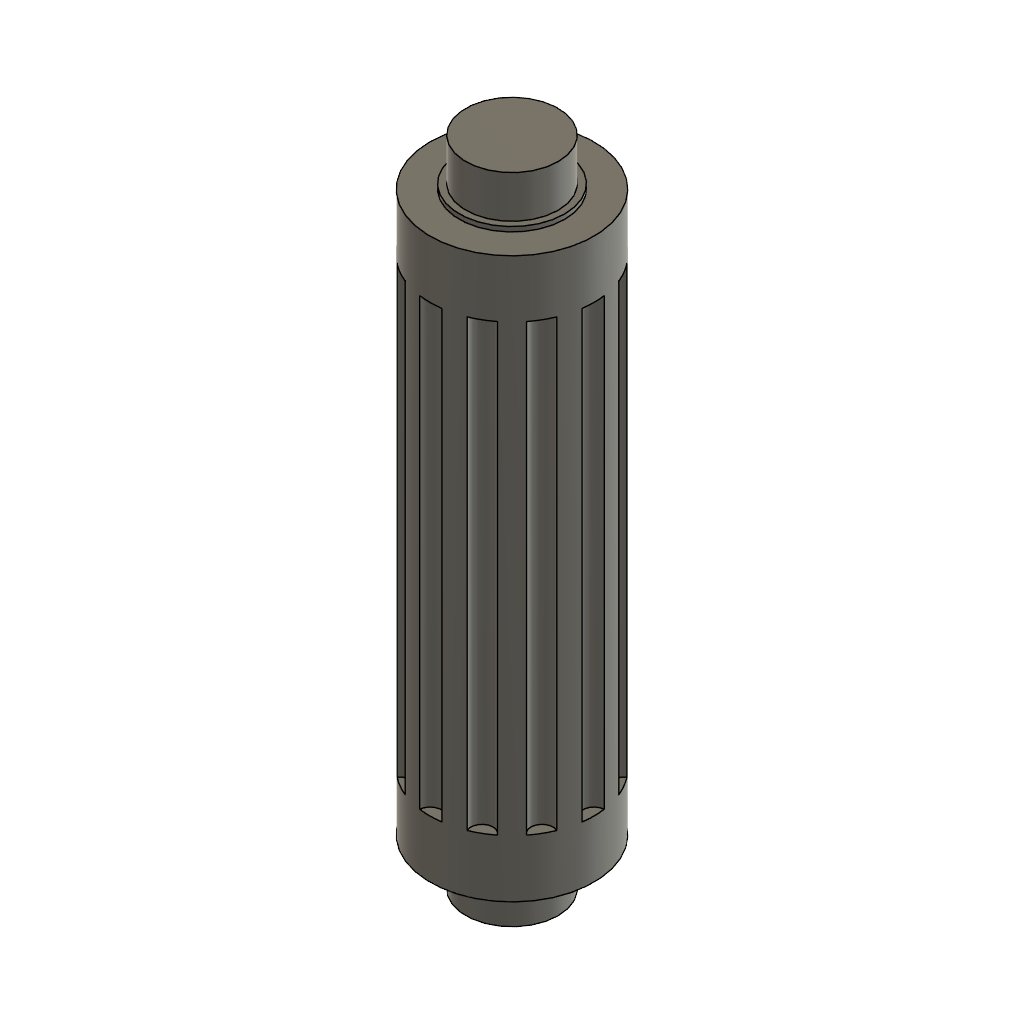
02-10_아이들롤러 (Autodesk Fusion 360 design; units mm, degrees)
Autodesk Fusion 360 part; units mm, degrees
sketch "스케치1" plane through (0, 0, 0) normal (0, 1, 0) x (1, 0, 0)
  circle A0 centre (0, 0) radius 7
  dimension "d1" = 14
  constraint coincident A0.centre origin
  measures "d1" diameter of A0
extrude "돌출1" add sketch "스케치1" along normal blind 47.8
sketch "스케치2" plane through (0, 47.8, 0) normal (0, 1, 0) x (-1, 0, 0)
  circle A0 centre (0, 0) radius 7
  circle A1 centre (0, 0) radius 4.5
  dimension "d4" = 9
  constraint coincident A0.centre A1.centre
  measures "d4" diameter of A1
extrude "돌출2" add sketch "스케치2" along normal blind 0.4 contours A1
sketch "스케치3" plane through (0, 48.2, 0) normal (0, 1, 0) x (-1, 0, 0)
  circle A0 centre (0, 0) radius 4.5
  circle A1 centre (0, 0) radius 3.95
  dimension "d7" = 7.9
  constraint coincident A0.centre A1.centre
  measures "d7" diameter of A1
extrude "돌출3" add sketch "스케치3" along normal blind 3.6 contours A1
sketch "스케치4" plane through (0, 0, 0) normal (0, -1, 0) x (1, 0, 0)
  circle A0 centre (0, 0) radius 7
  circle A1 centre (0, 0) radius 4.5
  dimension "d10" = 9
  constraint concentric A0 A1
  measures "d10" diameter of A1
extrude "돌출4" add sketch "스케치4" along normal blind 0.4 contours A1
sketch "스케치5" plane through (0, -0.4, 0) normal (0, -1, 0) x (1, 0, 0)
  circle A0 centre (0, 0) radius 4.5
  circle A1 centre (0, 0) radius 3.95
  dimension "d13" = 7.9
  constraint coincident A0.centre A1.centre
  measures "d13" diameter of A1
extrude "돌출5" add sketch "스케치5" along normal blind 3.6 contours A1
ref_plane "작업 평면1" through (0, 4.9, 0) normal (0, -1, 0) x (-1, 0, 0)
sketch "스케치6" plane through (0, 4.9, 0) normal (0, -1, 0) x (-1, 0, 0)
  circle A0 centre (-7, 0) radius 0.95
  circle A1 centre (-6.0622, -3.5) radius 0.95
  circle A2 centre (-3.5, -6.0622) radius 0.95
  circle A3 centre (0, -7) radius 0.95
  circle A4 centre (3.5, -6.0622) radius 0.95
  circle A5 centre (6.0622, -3.5) radius 0.95
  circle A6 centre (7, 0) radius 0.95
  circle A7 centre (6.0622, 3.5) radius 0.95
  circle A8 centre (3.5, 6.0622) radius 0.95
  circle A9 centre (0, 7) radius 0.95
  circle A10 centre (-3.5, 6.0622) radius 0.95
  circle A11 centre (-6.0622, 3.5) radius 0.95
  dimension "d18" = 1.9
  dimension "d20" = 360
  measures "d18" diameter of A0
extrude "돌출6" cut sketch "스케치6" against normal blind 38
